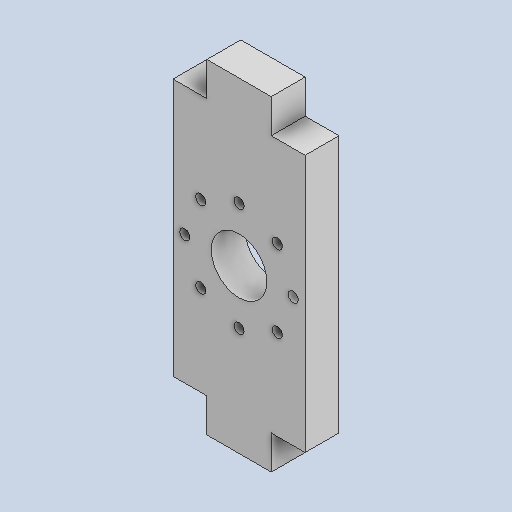
# Autodesk Inventor part: NeckConnectBot
Saved by Autodesk Inventor 2025.2 (Build 292293000, 293)
## iProperties
Created: 2025-06-29
Part Number: NeckConnectBot
Material: Generic
Document SubType Name: Modeling
Designer: ricoa
Density: 1 g/cm^3
Appearance: Default
Author: ricoa
Autodesk Inventor part; units mm, degrees
ref_plane "YZ Plane" through (0, 0, 0) normal (1, 0, 0) x (0, 1, 0)
ref_plane "XZ Plane" through (0, 0, 0) normal (0, 1, 0) x (-1, 0, 0)
ref_plane "XY Plane" through (0, 0, 0) normal (0, 0, 1) x (1, 0, 0)
sketch "Sketch1" plane through (0, 0, 0) normal (0, 0, 1) x (1, 0, 0)
  line L0 (0, 0) -> (9.5, 0) projected
  line L1 (0, 0) -> (0, 5) projected
  line L2 (-5, 5) -> (0, 5) projected
  line L3 (9.5, 5) -> (14.5, 5) projected
  line L4 (9.5, 0) -> (9.5, 5) projected
  line L5 (9.5, 43) -> (14.5, 43) projected
  line L6 (0, 48) -> (9.5, 48) projected
  line L7 (0, 43) -> (0, 48) projected
  line L8 (9.5, 43) -> (9.5, 48) projected
  line L9 (-5, 43) -> (0, 43) projected
  line L10 (4.75, 0) -> (4.75, 48) construction
  circle A0 centre (4.75, 24) radius 4.1
  line L11 (4.75, 24) -> (4.75, 16)
  circle A1 centre (4.75, 16) radius 0.75
  circle A2 centre (4.75, 24) radius 9.75 construction
  circle A3 centre (10.4069, 18.3431) radius 0.75
  circle A4 centre (12.75, 24) radius 0.75
  circle A5 centre (10.4069, 29.6569) radius 0.75
  circle A6 centre (4.75, 32) radius 0.75
  circle A7 centre (-0.9069, 29.6569) radius 0.75
  circle A8 centre (-3.25, 24) radius 0.75
  circle A9 centre (-0.9069, 18.3431) radius 0.75
  line L12 (-5, 5) -> (-5, 43)
  line L13 (14.5, 5) -> (14.5, 43)
  dimension "d0" = 8.2
  dimension "d1" = 8
  dimension "d2" = 1.5
  dimension "d3" = 19.5
  dimension "d6" = 360
  constraints: 10 centre point, 8 end point, 3 midpoint, 2 coincident, 1 parallel, 1 perpendicular, 1 point on line, 17 other
  measures "d0" diameter of A0
  measures "d1" distance of L11.start L11.end
  measures "d2" diameter of A1
  measures "d3" diameter of A2
extrude "Extrusion1" add sketch "Sketch1" along normal blind 5
body "Solid1"
